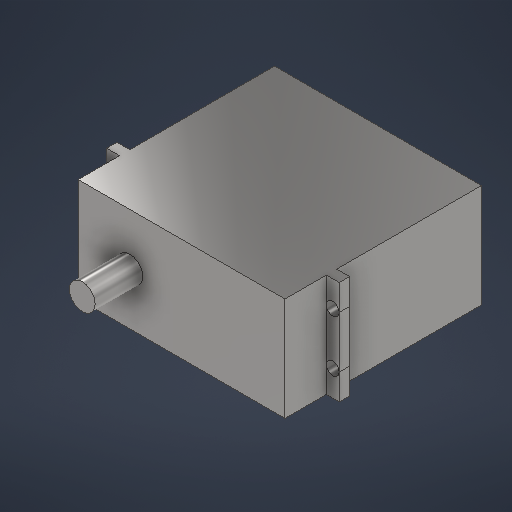
# Autodesk Inventor part: MG995 motor
Saved by Autodesk Inventor 2026.1 (Build 301233020, 233B)
## iProperties
Created: 2025-12-04
Part Number: MG995 motor
Material: Steel, Carbon
Document SubType Name: Modeling
Designer: kadir
Density: 7.85 g/cm^3
Appearance: Semi-Polished
Author: kadir
Autodesk Inventor part; units mm, degrees
ref_plane "YZ Plane" through (0, 0, 0) normal (1, 0, 0) x (0, 1, 0)
ref_plane "XZ Plane" through (0, 0, 0) normal (0, 1, 0) x (-1, 0, 0)
ref_plane "XY Plane" through (0, 0, 0) normal (0, 0, 1) x (1, 0, 0)
sketch "Sketch1" plane through (0, 0, 0) normal (0, 0, 1) x (1, 0, 0)
  line L0 (20, -10) -> (-20, -10)
  line L1 (-20, -10) -> (-20, 10)
  line L2 (-20, 10) -> (20, 10)
  line L3 (20, 10) -> (20, -10)
  line L4 (20, -10) -> (-20, 10) construction
  line L5 (-20, -10) -> (20, 10) construction
  point P0 (0, 0)
  dimension "d0" = 40
  dimension "d1" = 20
  constraints: 12 end point, 2 midpoint, 2 parallel, 1 horizontal, 1 perpendicular
  measures "d0" distance of L1.end L2.end
  measures "d1" distance of L0.end L1.end
extrude "Extrusion1" add sketch "Sketch1" along normal blind 28
sketch "Sketch2" plane through (0, 0, 28) normal (0, 0, 1) x (1, 0, 0)
  line L0 (-20, 10) -> (-20, -10) projected
  line L1 (-20, 10) -> (-22.5, 10)
  line L2 (-22.5, 10) -> (-22.5, -10)
  line L3 (-22.5, -10) -> (-20, -10)
  line L4 (-20, -10) -> (-20, 10)
  line L5 (20, 10) -> (-20, 10) projected
  line L6 (20, 10) -> (22.5, 10)
  line L7 (22.5, 10) -> (22.5, -10)
  line L8 (22.5, -10) -> (20, -10)
  line L9 (20, -10) -> (20, 10)
  circle A0 centre (-21.25, 5) radius 1.25
  circle A1 centre (-21.25, -5) radius 1.25
  circle A2 centre (21.25, -5) radius 1.25
  circle A3 centre (21.25, 5) radius 1.25
  point P0 (0, 0)
  point P1 (-20, -5)
  point P2 (-22.5, -5)
  point P3 (-22.5, 5)
  point P4 (-20, 5)
  point P5 (-21.25, 10)
  dimension "d4" = 2.5
  dimension "d5" = 20
  dimension "d6" = 2.5
  dimension "d15" = 5
  dimension "d16" = 5
  dimension "d17" = 2.5
  dimension "d18" = 2.5
  dimension "d19" = 5
  dimension "d20" = 5
  constraints: 16 end point, 4 centre point, 4 parallel, 2 horizontal, 2 perpendicular, 2 tangent, 1 midpoint
  measures "d4" distance of L3.end L2.end
  measures "d5" distance of L2.end L1.end
  measures "d6" distance of L7.end L8.end
  measures "d15" distance of A0.centre point (-21.25, 10)
  measures "d16" distance from line of L3 A1.centre
  measures "d17" diameter of A3
  measures "d18" diameter of A2
  measures "d19" distance from line of A3.centre L6
  measures "d20" distance from line of A2.centre L8
extrude "Extrusion2" add sketch "Sketch2" along normal blind 2 contours L0 A0 L2 L1 | L6 L7 A3 L9 | L0 A1 L2 A0 | L0 L3 L2 A1 | A3 L7 A2 L9 | A2 L7 L8 L9
sketch "Sketch3" plane through (0, 0, 28) normal (0, 0, 1) x (1, 0, 0)
  line L0 (-20, -10) -> (20, -10) projected
  line L1 (20, 10) -> (-20, 10)
  line L2 (-20, 10) -> (-20, -10)
  line L3 (-20, -10) -> (20, -10)
  line L4 (20, -10) -> (20, 10)
  line L5 (20, 10) -> (-20, -10) construction
  line L6 (-20, 10) -> (20, -10) construction
  point P0 (0, 0)
  constraints: 12 end point, 2 midpoint, 2 parallel, 1 horizontal, 1 perpendicular
extrude "Extrusion3" add sketch "Sketch3" along normal blind 10
sketch "Sketch4" plane through (0, 0, 38) normal (0, 0, 1) x (1, 0, 0)
  circle A0 centre (-10, 0) radius 2.5
  line L0 (-20, 10) -> (-20, -10) projected
  point P0 (0, 0)
  point P1 (-20, 0)
  dimension "d11" = 5
  dimension "d12" = 10
  constraints: 1 centre point, 1 midpoint
  measures "d11" diameter of A0
  measures "d12" distance of A0.centre point (-20, 0)
extrude "Extrusion4" add sketch "Sketch4" along normal blind 9.2
body "Solid1"
